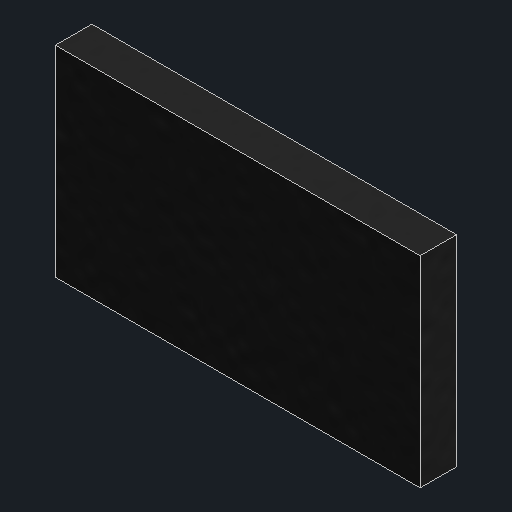
# Autodesk Inventor part: dupont_1x10_housing
Saved by Autodesk Inventor 2027.1 (Build 311270010, 270A)
## iProperties
Created: 2026-10-29
Part Number: dupont_1x10_housing
Material: Generic
Document SubType Name: Modeling
Designer: alexg
Density: 1 g/cm^3
Appearance: Black
Author: alexg
Autodesk Inventor part; units mm, degrees
ref_plane "YZ Plane" through (0, 0, 0) normal (1, 0, 0) x (0, 1, 0)
ref_plane "XZ Plane" through (0, 0, 0) normal (0, 1, 0) x (-1, 0, 0)
ref_plane "XY Plane" through (0, 0, 0) normal (0, 0, 1) x (1, 0, 0)
sketch "Body sketch" plane through (0, 0, 0) normal (0, 1, 0) x (-1, 0, 0)
  line L0 (12.7, -1.27) -> (-12.7, -1.27)
  line L1 (-12.7, -1.27) -> (-12.7, 1.27)
  line L2 (-12.7, 1.27) -> (12.7, 1.27)
  line L3 (12.7, 1.27) -> (12.7, -1.27)
  constraints: 8 end point, 2 parallel, 1 horizontal, 1 perpendicular
extrude "Body" add sketch "Body sketch" along normal blind 14
sketch "Pin sockets sketch" plane through (0, 0, 0) normal (0, 1, 0) x (-1, 0, 0)
  line L0 (11.93, -0.5) -> (10.93, -0.5)
  line L1 (10.93, -0.5) -> (10.93, 0.5)
  line L2 (10.93, 0.5) -> (11.93, 0.5)
  line L3 (11.93, 0.5) -> (11.93, -0.5)
  line L4 (9.39, -0.5) -> (8.39, -0.5)
  line L5 (8.39, -0.5) -> (8.39, 0.5)
  line L6 (8.39, 0.5) -> (9.39, 0.5)
  line L7 (9.39, 0.5) -> (9.39, -0.5)
  line L8 (6.85, -0.5) -> (5.85, -0.5)
  line L9 (5.85, -0.5) -> (5.85, 0.5)
  line L10 (5.85, 0.5) -> (6.85, 0.5)
  line L11 (6.85, 0.5) -> (6.85, -0.5)
  line L12 (4.31, -0.5) -> (3.31, -0.5)
  line L13 (3.31, -0.5) -> (3.31, 0.5)
  line L14 (3.31, 0.5) -> (4.31, 0.5)
  line L15 (4.31, 0.5) -> (4.31, -0.5)
  line L16 (1.77, -0.5) -> (0.77, -0.5)
  line L17 (0.77, -0.5) -> (0.77, 0.5)
  line L18 (0.77, 0.5) -> (1.77, 0.5)
  line L19 (1.77, 0.5) -> (1.77, -0.5)
  line L20 (-0.77, -0.5) -> (-1.77, -0.5)
  line L21 (-1.77, -0.5) -> (-1.77, 0.5)
  line L22 (-1.77, 0.5) -> (-0.77, 0.5)
  line L23 (-0.77, 0.5) -> (-0.77, -0.5)
  line L24 (-3.31, -0.5) -> (-4.31, -0.5)
  line L25 (-4.31, -0.5) -> (-4.31, 0.5)
  line L26 (-4.31, 0.5) -> (-3.31, 0.5)
  line L27 (-3.31, 0.5) -> (-3.31, -0.5)
  line L28 (-5.85, -0.5) -> (-6.85, -0.5)
  line L29 (-6.85, -0.5) -> (-6.85, 0.5)
  line L30 (-6.85, 0.5) -> (-5.85, 0.5)
  line L31 (-5.85, 0.5) -> (-5.85, -0.5)
  line L32 (-8.39, -0.5) -> (-9.39, -0.5)
  line L33 (-9.39, -0.5) -> (-9.39, 0.5)
  line L34 (-9.39, 0.5) -> (-8.39, 0.5)
  line L35 (-8.39, 0.5) -> (-8.39, -0.5)
  line L36 (-10.93, -0.5) -> (-11.93, -0.5)
  line L37 (-11.93, -0.5) -> (-11.93, 0.5)
  line L38 (-11.93, 0.5) -> (-10.93, 0.5)
  line L39 (-10.93, 0.5) -> (-10.93, -0.5)
  constraints: 80 end point, 20 parallel, 10 horizontal, 10 perpendicular
extrude "Pin sockets" cut sketch "Pin sockets sketch" along normal blind 7
body "Solid1"
